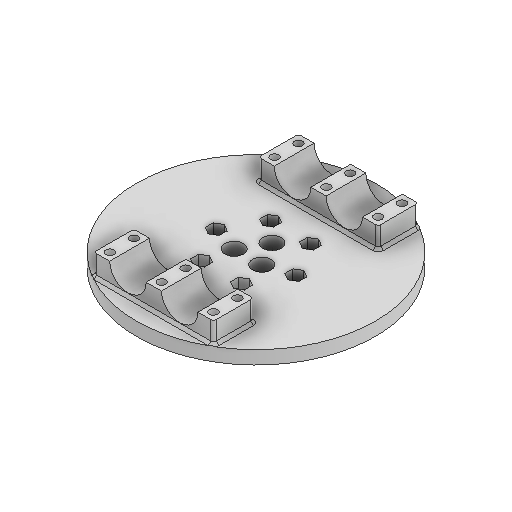
# Autodesk Inventor part: 3DP_PLA_B_Axis_Rotating_Stage
Saved by Autodesk Inventor 2027 (Build 310192060, 192F)
## iProperties
Created: 2026-01-17
Part Number: 3DP_PLA_B_Axis_Rotating_Stage
Material: Generic
Document SubType Name: Modeling
Designer: User
Density: 1 g/cm^3
Appearance: Default
Author: User
Autodesk Inventor part; units mm, degrees
ref_plane "YZ Plane" through (0, 0, 0) normal (1, 0, 0) x (0, 1, 0)
ref_plane "XZ Plane" through (0, 0, 0) normal (0, 1, 0) x (-1, 0, 0)
ref_plane "XY Plane" through (0, 0, 0) normal (0, 0, 1) x (1, 0, 0)
sketch "Sketch1" plane through (0, 0, 0) normal (0, 1, 0) x (-1, 0, 0)
  circle A0 centre (0, 0) radius 46
  circle A1 centre (0, 0) radius 90
  circle A2 centre (0, 0) radius 40
  dimension "d0" = 92
  dimension "d1" = 180
  dimension "d2" = 80
  constraints: 3 centre point, 3 coincident
  measures "d0" diameter of A0
  measures "d1" diameter of A1
  measures "d2" diameter of A2
extrude "Extrusion1" add sketch "Sketch1" along normal blind 10 contours A0 | A1 | A2
extrude "Extrusion2" add sketch "Sketch1" against normal blind 11 contours A0 | A2
sketch "Sketch2" plane through (0, 10, 0) normal (0, 1, 0) x (1, 0, 0)
  circle A0 centre (0, 0) radius 90 projected
  line L0 (-45, 77) -> (45, 77)
  line L1 (45, 77) -> (45, 47)
  line L2 (45, 47) -> (-45, 47)
  line L3 (-45, 47) -> (-45, 77)
  line L4 (45, -77) -> (-45, -77)
  line L5 (-45, -77) -> (-45, -47)
  line L6 (-45, -47) -> (45, -47)
  line L7 (45, -47) -> (45, -77)
  dimension "d7" = 90
  dimension "d8" = 30
  dimension "d9" = 45
  dimension "d10" = 47
  dimension "d11" = 30
  dimension "d12" = 90
  dimension "d13" = 47
  dimension "d14" = 45
  constraints: 16 end point, 4 parallel, 2 horizontal, 2 perpendicular
  measures "d7" distance of L1.end L2.end
  measures "d8" distance of L2.end L0.start
  measures "d9" distance from line of point (0, 0) L1
  measures "d10" distance from line of point (0, 0) L2
  measures "d11" distance of L4.end L5.end
  measures "d12" distance of L4.start L4.end
  measures "d13" distance from line of point (0, 0) L6
  measures "d14" distance from line of point (0, 0) L5
extrude "Extrusion3" add sketch "Sketch2" along normal blind 16 contours L0 L1 L2 L3 | L4 L5 L6 L7
sketch "Sketch3" plane through (45, 10, -77) normal (0, 0, -1) x (-1, 0, 0)
  line L0 (90, 0) -> (0, 0) projected
  line L1 (90, 0) -> (90, 16) projected
  line L2 (0, 16) -> (90, 16) projected
  line L3 (0, 0) -> (0, 16) projected
  circle A0 centre (25.5, 16) radius 13.75
  circle A1 centre (64.5, 16) radius 13.75
  point P0 (45, -10)
  dimension "d17" = 27.5
  dimension "d18" = 27.5
  dimension "d19" = 90
  dimension "d20" = 39
  dimension "d21" = 25.5
  constraints: 2 centre point, 2 point on line
  measures "d17" diameter of A0
  measures "d18" diameter of A1
  measures "d19" distance of L2.start L1.end
  measures "d20" distance of A1.centre A0.centre
  measures "d21" distance from line of L3 A0.centre
extrude "Extrusion4" cut sketch "Sketch3" against normal through all contours A1 L2 | L2 A1 | A0 L2 | L2 A0
sketch "Sketch4" plane through (0, 26, 0) normal (0, 1, 0) x (1, 0, 0)
  line L0 (33.25, 77) -> (33.25, 47) projected
  line L1 (33.25, 47) -> (45, 47) projected
  line L2 (45, 47) -> (45, 77) projected
  line L3 (45, 77) -> (33.25, 77) projected
  line L4 (-5.75, 77) -> (-5.75, 47) projected
  line L5 (-5.75, 47) -> (5.75, 47) projected
  line L6 (5.75, 47) -> (5.75, 77) projected
  line L7 (5.75, 77) -> (-5.75, 77) projected
  line L8 (-33.25, 47) -> (-33.25, 77) projected
  line L9 (-33.25, 77) -> (-45, 77) projected
  line L10 (-45, 77) -> (-45, 47) projected
  line L11 (-45, 47) -> (-33.25, 47) projected
  point P0 (0, 0)
  point P1 (39, 53)
  point P2 (39, 71)
  point P3 (0, 53)
  point P4 (0, 71)
  point P5 (-39, 53)
  point P6 (-39, 71)
  dimension "d24" = 6
  dimension "d25" = 6
  dimension "d26" = 39
  dimension "d27" = 39
  constraints: 4 horizontal alignment, 4 vertical alignment
  measures "d24" distance from line of L1 point (39, 53)
  measures "d25" distance from line of L3 point (39, 71)
  measures "d26" distance of point (0, 53) point (39, 53)
  measures "d27" distance of point (-39, 53) point (0, 53)
hole "Hole1" at (39, 26, -53) at (39, 26, -71) at (0, 26, -53) at (0, 26, -71) at (-39, 26, -53) at (-39, 26, -71) direction (0, -1, 0) diameter 6.2 end through all
mirror "Mirror1" about plane through (0, 0, 0) normal (0, 0, 1) of "Hole1"
fillet "Fillet1" radius 2 8 edges at (45, 18, -77) (45, 18, -47) (-45, 18, -77) (-45, 18, -47) (45, 18, 47) (45, 18, 77) (-45, 18, 47) (-45, 18, 77)
sketch "Sketch5" plane through (0, 0, 0) normal (0, -1, 0) x (1, 0, 0)
  circle A0 centre (-39, 71) radius 3.1 projected
  circle A1 centre (39, 53) radius 3.1 projected
  circle A2 centre (39, 71) radius 3.1 projected
  circle A3 centre (0, 53) radius 3.1 projected
  circle A4 centre (0, 71) radius 3.1 projected
  circle A5 centre (-39, 53) radius 3.1 projected
  circle A6 centre (-39, -71) radius 3.1 projected
  circle A7 centre (-39, -53) radius 3.1 projected
  circle A8 centre (0, -71) radius 3.1 projected
  circle A9 centre (0, -53) radius 3.1 projected
  circle A10 centre (39, -71) radius 3.1 projected
  circle A11 centre (39, -53) radius 3.1 projected
  circle A12 centre (0, 0) radius 46 projected
  circle A13 centre (0, 0) radius 90 projected
  line L0 (44.25, -56.0311) -> (39, -59.0622)
  line L1 (39, -59.0622) -> (33.75, -56.0311)
  line L2 (33.75, -56.0311) -> (33.75, -49.9689)
  line L3 (33.75, -49.9689) -> (39, -46.9378)
  line L4 (39, -46.9378) -> (44.25, -49.9689)
  line L5 (44.25, -49.9689) -> (44.25, -56.0311)
  line L6 (44.25, -74.0311) -> (39, -77.0622)
  line L7 (39, -77.0622) -> (33.75, -74.0311)
  line L8 (33.75, -74.0311) -> (33.75, -67.9689)
  line L9 (33.75, -67.9689) -> (39, -64.9378)
  line L10 (39, -64.9378) -> (44.25, -67.9689)
  line L11 (44.25, -67.9689) -> (44.25, -74.0311)
  line L12 (5.25, -56.0311) -> (0, -59.0622)
  line L13 (0, -59.0622) -> (-5.25, -56.0311)
  line L14 (-5.25, -56.0311) -> (-5.25, -49.9689)
  line L15 (-5.25, -49.9689) -> (0, -46.9378)
  line L16 (0, -46.9378) -> (5.25, -49.9689)
  line L17 (5.25, -49.9689) -> (5.25, -56.0311)
  line L18 (5.25, -74.0311) -> (0, -77.0622)
  line L19 (0, -77.0622) -> (-5.25, -74.0311)
  line L20 (-5.25, -74.0311) -> (-5.25, -67.9689)
  line L21 (-5.25, -67.9689) -> (0, -64.9378)
  line L22 (0, -64.9378) -> (5.25, -67.9689)
  line L23 (5.25, -67.9689) -> (5.25, -74.0311)
  line L24 (-33.75, -56.0311) -> (-39, -59.0622)
  line L25 (-39, -59.0622) -> (-44.25, -56.0311)
  line L26 (-44.25, -56.0311) -> (-44.25, -49.9689)
  line L27 (-44.25, -49.9689) -> (-39, -46.9378)
  line L28 (-39, -46.9378) -> (-33.75, -49.9689)
  line L29 (-33.75, -49.9689) -> (-33.75, -56.0311)
  line L30 (-33.75, -74.0311) -> (-39, -77.0622)
  line L31 (-39, -77.0622) -> (-44.25, -74.0311)
  line L32 (-44.25, -74.0311) -> (-44.25, -67.9689)
  line L33 (-44.25, -67.9689) -> (-39, -64.9378)
  line L34 (-39, -64.9378) -> (-33.75, -67.9689)
  line L35 (-33.75, -67.9689) -> (-33.75, -74.0311)
  line L36 (-33.75, 49.9689) -> (-39, 46.9378)
  line L37 (-39, 46.9378) -> (-44.25, 49.9689)
  line L38 (-44.25, 49.9689) -> (-44.25, 56.0311)
  line L39 (-44.25, 56.0311) -> (-39, 59.0622)
  line L40 (-39, 59.0622) -> (-33.75, 56.0311)
  line L41 (-33.75, 56.0311) -> (-33.75, 49.9689)
  line L42 (-33.75, 67.9689) -> (-39, 64.9378)
  line L43 (-39, 64.9378) -> (-44.25, 67.9689)
  line L44 (-44.25, 67.9689) -> (-44.25, 74.0311)
  line L45 (-44.25, 74.0311) -> (-39, 77.0622)
  line L46 (-39, 77.0622) -> (-33.75, 74.0311)
  line L47 (-33.75, 74.0311) -> (-33.75, 67.9689)
  line L48 (5.25, 49.9689) -> (0, 46.9378)
  line L49 (0, 46.9378) -> (-5.25, 49.9689)
  line L50 (-5.25, 49.9689) -> (-5.25, 56.0311)
  line L51 (-5.25, 56.0311) -> (0, 59.0622)
  line L52 (0, 59.0622) -> (5.25, 56.0311)
  line L53 (5.25, 56.0311) -> (5.25, 49.9689)
  line L54 (5.25, 67.9689) -> (0, 64.9378)
  line L55 (0, 64.9378) -> (-5.25, 67.9689)
  line L56 (-5.25, 67.9689) -> (-5.25, 74.0311)
  line L57 (-5.25, 74.0311) -> (0, 77.0622)
  line L58 (0, 77.0622) -> (5.25, 74.0311)
  line L59 (5.25, 74.0311) -> (5.25, 67.9689)
  line L60 (44.2666, 49.9978) -> (39.0333, 46.9379)
  line L61 (39.0333, 46.9379) -> (33.7667, 49.9401)
  line L62 (33.7667, 49.9401) -> (33.7334, 56.0022)
  line L63 (33.7334, 56.0022) -> (38.9667, 59.0621)
  line L64 (38.9667, 59.0621) -> (44.2333, 56.0599)
  line L65 (44.2333, 56.0599) -> (44.2666, 49.9978)
  line L66 (44.2666, 67.9978) -> (39.0333, 64.9379)
  line L67 (39.0333, 64.9379) -> (33.7667, 67.9401)
  line L68 (33.7667, 67.9401) -> (33.7334, 74.0022)
  line L69 (33.7334, 74.0022) -> (38.9667, 77.0621)
  line L70 (38.9667, 77.0621) -> (44.2333, 74.0599)
  line L71 (44.2333, 74.0599) -> (44.2666, 67.9978)
  point P0 (-33.75, 71)
  point P1 (5.25, 71)
  point P2 (44.2499, 71.0288)
  dimension "d36" = 10.5
  dimension "d37" = 10.5
  dimension "d38" = 10.5
  dimension "d39" = 10.5
  dimension "d40" = 10.5
  dimension "d41" = 10.5
  dimension "d42" = 10.5
  dimension "d43" = 10.5
  dimension "d44" = 10.5
  dimension "d45" = 10.5
  dimension "d46" = 10.5
  dimension "d47" = 10.5
  constraints: 144 end point, 12 coincident, 6 equal length, 3 midpoint, 3 point on line, 156 other
  measures "d36" distance between parallel lines of L2 L5
  measures "d37" distance between parallel lines of L11 L8
  measures "d38" distance between parallel lines of L14 L17
  measures "d39" distance between parallel lines of L23 L20
  measures "d40" distance between parallel lines of L26 L29
  measures "d41" distance between parallel lines of L35 L32
  measures "d42" distance between parallel lines of L44 L47
  measures "d43" distance between parallel lines of L38 L41
  measures "d44" distance between parallel lines of L56 L59
  measures "d45" distance between parallel lines of L50 L53
  measures "d46" distance between parallel lines of L68 L71
  measures "d47" distance between parallel lines of L62 L65
extrude "Extrusion5" cut sketch "Sketch5" against normal blind 5 contours A11 | L0 L1 L2 L3 L4 L5 | L6 L7 L8 L9 L10 L11 | L12 L13 L14 L15 L16 L17 | L18 L19 L20 L21 L22 L23 | L24 L25 L26 L27 L28 L29 | L30 L31 L32 L33 L34 L35 | L36 L37 L38 L39 L40 L41 | L42 L43 L44 L45 L46 L47 | L48 L49 L50 L51 L52 L53 | L54 L55 L56 L57 L58 L59 | L60 L61 L62 L63 L64 L65 | L66 L67 L68 L69 L70 L71
sketch "Sketch6" plane through (0, -11, 0) normal (0, -1, 0) x (1, 0, 0)
  circle A0 centre (0, 0) radius 46 projected
  point P0 (30, 0)
  point P1 (15, 25.9808)
  point P2 (-15, 25.9808)
  point P3 (-30, 0)
  point P4 (-15, -25.9808)
  point P5 (15, -25.9808)
  dimension "d50" = 30
  dimension "d53" = 360
  constraints: 7 other
  measures "d50" distance of point (0, 0) point (30, 0)
hole "Hole2" at (30, -11, 0) at (15, -11, 25.9808) at (-15, -11, 25.9808) at (-30, -11, 0) at (-15, -11, -25.9808) at (15, -11, -25.9808) direction (0, 1, 0) diameter 6.2 end through all
sketch "Sketch7" plane through (0, 10, 0) normal (0, 1, 0) x (1, 0, 0)
  circle A0 centre (15, 25.9808) radius 3.1 projected
  circle A1 centre (-15, 25.9808) radius 3.1 projected
  circle A2 centre (-30, 0) radius 3.1 projected
  circle A3 centre (-15, -25.9808) radius 3.1 projected
  circle A4 centre (15, -25.9808) radius 3.1 projected
  circle A5 centre (30, 0) radius 3.1 projected
  line L0 (-45, 49) -> (-45, 75) projected
  arc A6 (-43, 77) -> (-45, 75) centre (-43, 75) ccw projected
  line L1 (-43, 77) -> (43, 77) projected
  arc A7 (45, 75) -> (43, 77) centre (43, 75) ccw projected
  line L2 (45, 75) -> (45, 49) projected
  arc A8 (43, 47) -> (45, 49) centre (43, 49) ccw projected
  line L3 (43, 47) -> (-43, 47) projected
  arc A9 (-45, 49) -> (-43, 47) centre (-43, 49) ccw projected
  line L4 (45, -49) -> (45, -75) projected
  arc A10 (43, -77) -> (45, -75) centre (43, -75) ccw projected
  line L5 (43, -77) -> (-43, -77) projected
  arc A11 (-45, -75) -> (-43, -77) centre (-43, -75) ccw projected
  line L6 (-45, -75) -> (-45, -49) projected
  arc A12 (-43, -47) -> (-45, -49) centre (-43, -49) ccw projected
  line L7 (-43, -47) -> (43, -47) projected
  arc A13 (45, -49) -> (43, -47) centre (43, -49) ccw projected
  circle A14 centre (0, 0) radius 90 projected
  line L8 (20.25, 22.9497) -> (15, 19.9186)
  line L9 (15, 19.9186) -> (9.75, 22.9497)
  line L10 (9.75, 22.9497) -> (9.75, 29.0119)
  line L11 (9.75, 29.0119) -> (15, 32.0429)
  line L12 (15, 32.0429) -> (20.25, 29.0119)
  line L13 (20.25, 29.0119) -> (20.25, 22.9497)
  line L14 (-20.25, 22.9497) -> (-20.25, 29.0119)
  line L15 (-20.25, 29.0119) -> (-15, 32.0429)
  line L16 (-15, 19.9186) -> (-20.25, 22.9497)
  line L17 (-15, 32.0429) -> (-9.75, 29.0119)
  line L18 (-9.75, 29.0119) -> (-9.75, 22.9497)
  line L19 (-9.75, 22.9497) -> (-15, 19.9186)
  line L20 (-30, -6.0622) -> (-35.25, -3.0311)
  line L21 (-35.25, -3.0311) -> (-35.25, 3.0311)
  line L22 (-24.75, -3.0311) -> (-30, -6.0622)
  line L23 (-35.25, 3.0311) -> (-30, 6.0622)
  line L24 (-30, 6.0622) -> (-24.75, 3.0311)
  line L25 (-24.75, 3.0311) -> (-24.75, -3.0311)
  line L26 (-9.75, -29.0119) -> (-15, -32.0429)
  line L27 (-15, -32.0429) -> (-20.25, -29.0119)
  line L28 (-9.75, -22.9497) -> (-9.75, -29.0119)
  line L29 (-20.25, -29.0119) -> (-20.25, -22.9497)
  line L30 (-20.25, -22.9497) -> (-15, -19.9186)
  line L31 (-15, -19.9186) -> (-9.75, -22.9497)
  line L32 (20.25, -22.9497) -> (20.25, -29.0119)
  line L33 (20.25, -29.0119) -> (15, -32.0429)
  line L34 (15, -19.9186) -> (20.25, -22.9497)
  line L35 (15, -32.0429) -> (9.75, -29.0119)
  line L36 (9.75, -29.0119) -> (9.75, -22.9497)
  line L37 (9.75, -22.9497) -> (15, -19.9186)
  line L38 (30, 6.0622) -> (35.25, 3.0311)
  line L39 (35.25, 3.0311) -> (35.25, -3.0311)
  line L40 (24.75, 3.0311) -> (30, 6.0622)
  line L41 (35.25, -3.0311) -> (30, -6.0622)
  line L42 (30, -6.0622) -> (24.75, -3.0311)
  line L43 (24.75, -3.0311) -> (24.75, 3.0311)
  point P0 (-15, 25.9808)
  point P1 (-30, 0)
  point P2 (-15, -25.9808)
  point P3 (15, -25.9808)
  point P4 (30, 0)
  dimension "d62" = 10.5
  dimension "d65" = 360
  constraints: 72 end point, 1 coincident, 92 other
  measures "d62" distance between parallel lines of L10 L13
extrude "Extrusion6" cut sketch "Sketch7" against normal blind 10 contours L8 L9 L10 L11 L12 L13 | L14 L15 L17 L18 L19 L16 | L20 L21 L23 L24 L25 L22 | L26 L27 L29 L30 L31 L28 | L32 L33 L35 L36 L37 L34 | L38 L39 L41 L42 L43 L40
chamfer "Chamfer1" distance 2 angle 45 16 edges at (0, 10, 77) (-44.4142, 10, 76.4142) (-45, 10, 62) (-44.4142, 10, 47.5858) (0, 10, 47) (44.4142, 10, 47.5858) (45, 10, 62) (44.4142, 10, 76.4142) (0, 10, -47) (-44.4142, 10, -47.5858) (-45, 10, -62) (-44.4142, 10, -76.4142) (0, 10, -77) (44.4142, 10, -76.4142) (45, 10, -62) (44.4142, 10, -47.5858)
sketch "Sketch8" plane through (0, 10, 0) normal (0, 1, 0) x (1, 0, 0)
  point P0 (0, 0)
  point P1 (0, 12)
  point P2 (-10.3923, -6)
  point P3 (10.3923, -6)
  dimension "d72" = 12
  dimension "d75" = 360
  constraints: 4 other
  measures "d72" distance of point (0, 0) point (0, 12)
hole "Hole3" at (0, 10, -12) at (-10.3923, 10, 6) at (10.3923, 10, 6) direction (0, -1, 0) diameter 14 depth 27
equation "\"d9\" = 0.5 * d7"
equation "\"d11\" = d8"
equation "\"d12\" = d7"
equation "\"d13\" = d10"
equation "\"d14\" = d9"
equation "\"d21\" = -0.5 * d20 + 0.5 * d19"
equation "\"d25\" = d24"
equation "\"d27\" = d26"
equation "\"d37\" = d36"
equation "\"d38\" = d36"
equation "\"d39\" = d36"
equation "\"d40\" = d36"
equation "\"d41\" = d36"
equation "\"d42\" = d36"
equation "\"d43\" = d36"
equation "\"d44\" = d36"
equation "\"d45\" = d36"
equation "\"d46\" = d36"
equation "\"d47\" = d36"
body "Solid1"
